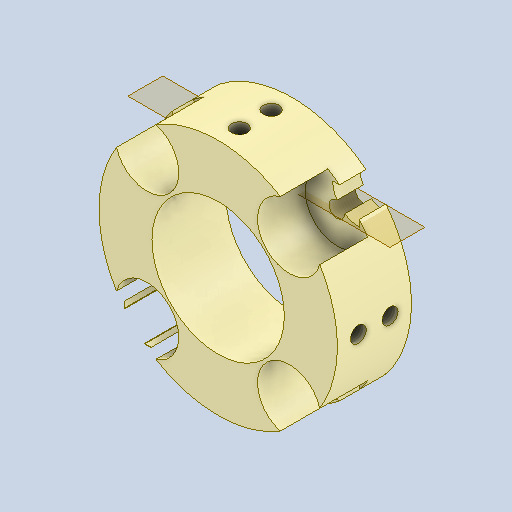
# Autodesk Inventor part: 零件1 - 副本
Saved by Autodesk Inventor 2025 (Build 290162000, 162)
## iProperties
Created: 2026-11-03
Part Number: 零件1 - 副本
Material: 尼龙 6/6
Document SubType Name: Modeling
Designer: test
Density: 1.13 g/cm^3
Appearance: 尼龙 6
Author: test
Autodesk Inventor part; units mm, degrees
ref_plane "YZ Plane" through (0, 0, 0) normal (1, 0, 0) x (0, 1, 0)
ref_plane "XY Plane" through (0, 0, 0) normal (0, 0, 1) x (1, 0, 0)
sketch "草图1" plane through (0, 0, 0) normal (0, 0, 1) x (1, 0, 0)
  circle A0 centre (0, 0) radius 22.5
  dimension "d0" = 45
  constraints: 1 centre point, 1 coincident
  measures "d0" diameter of A0
extrude "拉伸1" add sketch "草图1" along normal blind 8
sketch "草图2" plane through (0, 0, 8) normal (0, 0, 1) x (1, 0, 0)
  circle A0 centre (0, 0) radius 19
  line L0 (-13.435, -13.435) -> (13.435, -13.435)
  line L1 (13.435, -13.435) -> (13.435, 13.435)
  line L2 (13.435, 13.435) -> (-13.435, 13.435)
  line L3 (-13.435, 13.435) -> (-13.435, -13.435)
  line L4 (-13.435, -13.435) -> (13.435, 13.435) construction
  line L5 (13.435, -13.435) -> (-13.435, 13.435) construction
  circle A1 centre (-13.435, 13.435) radius 1.5
  circle A2 centre (13.435, 13.435) radius 1.5
  circle A3 centre (13.435, -13.435) radius 1.5
  circle A4 centre (-13.435, -13.435) radius 1.5
  dimension "d3" = 38
  dimension "d4" = 3
  dimension "d5" = 3
  dimension "d6" = 3
  dimension "d7" = 3
  constraints: 12 end point, 5 centre point, 4 coincident, 2 midpoint, 2 parallel, 2 perpendicular, 2 point on circle, 1 horizontal
  measures "d3" diameter of A0
  measures "d4" diameter of A1
  measures "d5" diameter of A2
  measures "d6" diameter of A3
  measures "d7" diameter of A4
extrude "拉伸2" cut sketch "草图2" against normal through all contours A2 L1 A0 | A0 A2 | A3 A0 | A0 L1 A3 | L2 A2 A0 | L1 A2 L2 | A0 A3 L0 | L0 A3 L1 | A1 L2 A0 | A0 A1 | A1 L3 L2 | A4 A0 | A0 L0 A4 | L0 L3 A4 | L3 A1 A0 | A0 A4 L3
ref_plane "工作平面1" through (0, 13.5, 0) normal (0, 1, 0) x (-1, 0, 0)
sketch "草图4" plane through (0, 13.5, 0) normal (0, 1, 0) x (-1, 0, 0)
  circle A0 centre (0, 4) radius 1.5
  line L0 (22.5, 8) -> (-22.5, 8) projected
  point P0 (0, 0)
  dimension "d13" = 3
  dimension "d14" = 4
  constraints: 1 centre point
  measures "d13" diameter of A0
  measures "d14" distance from line of A0.centre L0
extrude "拉伸3" cut sketch "草图4" along normal blind 10
thread "螺纹1" size "M3x0.5" designation "M3" class "6H" standard "GB Metric profile" length 15.103
pattern_circular "环形阵列1" count 4 over 360 about axis through (0, 0, 0) along (0, 0, 1) of "拉伸3"
thread "螺纹2" size "M3x0.5" designation "M3" class "6H" standard "GB Metric profile" length 15.103
thread "螺纹3" size "M3x0.5" designation "M3" class "6H" standard "GB Metric profile" length 15.103
thread "螺纹4" size "M3x0.5" designation "M3" class "6H" standard "GB Metric profile" length 15.103
thread "螺纹5" size "M3x0.5" designation "M3" class "6H" standard "GB Metric profile" length 15.103
sketch "草图5" plane through (0, 0, 8) normal (0, 0, 1) x (1, 0, 0)
  circle A0 centre (13.435, -13.435) radius 1.5 projected
  circle A1 centre (13.435, 13.435) radius 1.5 projected
  circle A2 centre (-13.435, -13.435) radius 1.5 projected
  circle A3 centre (-13.435, 13.435) radius 1.5 projected
  circle A4 centre (0, 0) radius 22.5 projected
  circle A5 centre (-13.435, -13.435) radius 3
  circle A6 centre (-13.435, 13.435) radius 3
  circle A7 centre (13.435, 13.435) radius 3
  circle A8 centre (13.435, -13.435) radius 3
  dimension "d30" = 6
  dimension "d31" = 6
  dimension "d32" = 6
  dimension "d33" = 6
  constraints: 4 centre point, 4 coincident
  measures "d30" diameter of A5
  measures "d31" diameter of A6
  measures "d32" diameter of A7
  measures "d33" diameter of A8
extrude "拉伸4" cut sketch "草图5" against normal blind 3 contours A5 | A6 | A7 | A8
sketch "草图6" plane through (0, 0, 8) normal (0, 0, 1) x (1, 0, 0)
  circle A0 centre (0, 0) radius 25
  line L0 (-17.6777, -17.6777) -> (17.6777, -17.6777)
  line L1 (17.6777, -17.6777) -> (17.6777, 17.6777)
  line L2 (17.6777, 17.6777) -> (-17.6777, 17.6777)
  line L3 (-17.6777, 17.6777) -> (-17.6777, -17.6777)
  line L4 (-17.6777, -17.6777) -> (17.6777, 17.6777) construction
  line L5 (17.6777, -17.6777) -> (-17.6777, 17.6777) construction
  circle A1 centre (-17.6777, 17.6777) radius 5.05
  circle A2 centre (17.6777, 17.6777) radius 5.05
  circle A3 centre (17.6777, -17.6777) radius 5.05
  circle A4 centre (-17.6777, -17.6777) radius 5.05
  point P0 (-12.6277, -17.6777)
  point P1 (-17.6777, -12.6277)
  point P2 (17.6777, -12.6277)
  point P3 (12.6277, -17.6777)
  point P4 (12.6277, 17.6777)
  point P5 (17.6777, 12.6277)
  point P6 (-17.6777, 12.6277)
  point P7 (-12.6277, 17.6777)
  dimension "d36" = 50
  dimension "d37" = 10.1
  dimension "d38" = 10.1
  dimension "d39" = 10.1
  dimension "d40" = 10.1
  constraints: 12 end point, 5 coincident, 4 centre point, 2 midpoint, 2 parallel, 2 perpendicular, 1 horizontal, 3 other
  measures "d37" diameter of A1
  measures "d38" diameter of A2
  measures "d39" diameter of A3
  measures "d40" diameter of A4
extrude "拉伸5" cut sketch "草图6" against normal blind 8 contours L1 A2 L2 | L0 A3 L1 | A1 L3 L2 | L0 L3 A4
sketch "草图7" plane through (0, 0, 8) normal (0, 0, 1) x (1, 0, 0)
  arc A0 (17.6777, -12.6277) -> (16.3672, -12.8007) centre (17.6777, -17.6777) ccw projected
  line L0 (17.6777, -12.6277) -> (17.6777, -13.9194) projected
  arc A1 (17.6777, -13.9194) -> (17.6777, 13.9194) centre (0, 0) ccw projected
  line L1 (17.6777, 13.9194) -> (17.6777, 12.6277) projected
  arc A2 (16.3672, 12.8007) -> (17.6777, 12.6277) centre (17.6777, 17.6777) ccw projected
  arc A3 (12.8007, 16.3672) -> (16.3672, 12.8007) centre (13.435, 13.435) ccw projected
  arc A4 (12.6277, 17.6777) -> (12.8007, 16.3672) centre (17.6777, 17.6777) ccw projected
  line L2 (12.6277, 17.6777) -> (13.9194, 17.6777) projected
  arc A5 (13.9194, 17.6777) -> (-13.9194, 17.6777) centre (0, 0) ccw projected
  line L3 (-13.9194, 17.6777) -> (-12.6277, 17.6777) projected
  arc A6 (-12.8007, 16.3672) -> (-12.6277, 17.6777) centre (-17.6777, 17.6777) ccw projected
  arc A7 (-16.3672, 12.8007) -> (-12.8007, 16.3672) centre (-13.435, 13.435) ccw projected
  arc A8 (-17.6777, 12.6277) -> (-16.3672, 12.8007) centre (-17.6777, 17.6777) ccw projected
  line L4 (-17.6777, 12.6277) -> (-17.6777, 13.9194) projected
  arc A9 (-17.6777, 13.9194) -> (-17.6777, -13.9194) centre (0, 0) ccw projected
  line L5 (-17.6777, -13.9194) -> (-17.6777, -12.6277) projected
  arc A10 (-16.3672, -12.8007) -> (-17.6777, -12.6277) centre (-17.6777, -17.6777) ccw projected
  arc A11 (-12.8007, -16.3672) -> (-16.3672, -12.8007) centre (-13.435, -13.435) ccw projected
  arc A12 (-12.6277, -17.6777) -> (-12.8007, -16.3672) centre (-17.6777, -17.6777) ccw projected
  line L6 (-12.6277, -17.6777) -> (-13.9194, -17.6777) projected
  arc A13 (-13.9194, -17.6777) -> (13.9194, -17.6777) centre (0, 0) ccw projected
  line L7 (13.9194, -17.6777) -> (12.6277, -17.6777) projected
  arc A14 (12.8007, -16.3672) -> (12.6277, -17.6777) centre (17.6777, -17.6777) ccw projected
  arc A15 (16.3672, -12.8007) -> (12.8007, -16.3672) centre (13.435, -13.435) ccw projected
extrude "拉伸6" add sketch "草图7" along normal blind 6
pattern_linear "矩形阵列1" count 2 spacing 6 along (0, 0, 1) of "拉伸3", "环形阵列1", "拉伸1"
sketch "草图9" plane through (-12.6277, -17.6777, 6) normal (0, 0, -1) x (-1, 0, 0)
  line L0 (1.2917, 0) -> (0, 0) projected
  arc A0 (1.2917, 0) -> (5.05, 3.7583) centre (-12.6277, 17.6777) ccw projected
  line L1 (5.05, 5.05) -> (5.05, 3.7583) projected
  arc A1 (5.05, 5.05) -> (3.7395, 4.877) centre (5.05, 0) ccw projected
  arc A2 (3.7395, 4.877) -> (0.173, 1.3105) centre (0.8074, 4.2426) ccw projected
  arc A3 (0.173, 1.3105) -> (0, 0) centre (5.05, 0) ccw projected
  line L2 (5.05, 31.5971) -> (5.05, 30.3053) projected
  arc A4 (5.05, 31.5971) -> (1.2917, 35.3553) centre (-12.6277, 17.6777) ccw projected
  line L3 (0, 35.3553) -> (1.2917, 35.3553) projected
  arc A5 (0, 35.3553) -> (0.173, 34.0449) centre (5.05, 35.3553) ccw projected
  arc A6 (0.173, 34.0449) -> (3.7395, 30.4783) centre (0.8074, 31.1127) ccw projected
  arc A7 (3.7395, 30.4783) -> (5.05, 30.3053) centre (5.05, 35.3553) ccw projected
  line L4 (-30.3053, 30.3053) -> (-30.3053, 31.5971) projected
  arc A8 (-30.3053, 30.3053) -> (-28.9949, 30.4783) centre (-30.3053, 35.3553) ccw projected
  arc A9 (-28.9949, 30.4783) -> (-25.4283, 34.0449) centre (-26.0627, 31.1127) ccw projected
  arc A10 (-25.4283, 34.0449) -> (-25.2553, 35.3553) centre (-30.3053, 35.3553) ccw projected
  line L5 (-26.5471, 35.3553) -> (-25.2553, 35.3553) projected
  arc A11 (-26.5471, 35.3553) -> (-30.3053, 31.5971) centre (-12.6277, 17.6777) ccw projected
  line L6 (-25.2553, 0) -> (-26.5471, 0) projected
  arc A12 (-25.2553, 0) -> (-25.4283, 1.3105) centre (-30.3053, 0) ccw projected
  arc A13 (-25.4283, 1.3105) -> (-28.9949, 4.877) centre (-26.0627, 4.2426) ccw projected
  arc A14 (-28.9949, 4.877) -> (-30.3053, 5.05) centre (-30.3053, 0) ccw projected
  line L7 (-30.3053, 3.7583) -> (-30.3053, 5.05) projected
  arc A15 (-30.3053, 3.7583) -> (-26.5471, 0) centre (-12.6277, 17.6777) ccw projected
extrude "拉伸8" cut sketch "草图9" against normal blind 16.5
sketch "草图10" plane through (0, 0, 14) normal (0, 0, 1) x (1, 0, 0)
  circle A0 centre (0, 0) radius 12.5
  dimension "d52" = 25
  constraints: 1 centre point, 1 coincident
  measures "d52" diameter of A0
extrude "拉伸9" cut sketch "草图10" against normal through all
sketch "草图12" plane through (0, 0, 14) normal (0, 0, 1) x (1, 0, 0)
  arc A0 (-12.8007, -16.3672) -> (-16.3672, -12.8007) centre (-13.435, -13.435) ccw projected
  arc A1 (-12.6277, -17.6777) -> (-13.4373, -14.935) centre (-17.6777, -17.6777) ccw projected
  circle A2 centre (-13.435, -13.435) radius 4.3188
  circle A3 centre (0, 0) radius 12.5 projected
  line L0 (17.6777, 13.9194) -> (17.6777, 12.6277) projected
  arc A4 (16.3672, 12.8007) -> (17.6777, 12.6277) centre (17.6777, 17.6777) ccw projected
  arc A5 (12.8007, 16.3672) -> (16.3672, 12.8007) centre (13.435, 13.435) ccw projected
  arc A6 (12.6277, 17.6777) -> (12.8007, 16.3672) centre (17.6777, 17.6777) ccw projected
  line L1 (12.6277, 17.6777) -> (13.9194, 17.6777) projected
  arc A7 (13.9194, 17.6777) -> (-13.9194, 17.6777) centre (0, 0) ccw projected
  line L2 (-13.9194, 17.6777) -> (-12.6277, 17.6777) projected
  arc A8 (-12.8007, 16.3672) -> (-12.6277, 17.6777) centre (-17.6777, 17.6777) ccw projected
  arc A9 (-16.3672, 12.8007) -> (-12.8007, 16.3672) centre (-13.435, 13.435) ccw projected
  arc A10 (-17.6777, 12.6277) -> (-16.3672, 12.8007) centre (-17.6777, 17.6777) ccw projected
  line L3 (-17.6777, 12.6277) -> (-17.6777, 13.9194) projected
  arc A11 (-17.6777, 13.9194) -> (-17.6777, -13.9194) centre (0, 0) ccw projected
  line L4 (-17.6777, -13.9194) -> (-17.6777, -12.6277) projected
  arc A12 (-16.3672, -12.8007) -> (-17.6777, -12.6277) centre (-17.6777, -17.6777) ccw projected
  arc A13 (-12.8007, -16.3672) -> (-16.3672, -12.8007) centre (-13.435, -13.435) ccw projected
  arc A14 (-12.6277, -17.6777) -> (-12.8007, -16.3672) centre (-17.6777, -17.6777) ccw projected
  line L5 (-12.6277, -17.6777) -> (-13.9194, -17.6777) projected
  arc A15 (-13.9194, -17.6777) -> (13.9194, -17.6777) centre (0, 0) ccw projected
  line L6 (13.9194, -17.6777) -> (12.6277, -17.6777) projected
  arc A16 (12.8007, -16.3672) -> (12.6277, -17.6777) centre (17.6777, -17.6777) ccw projected
  arc A17 (16.3672, -12.8007) -> (12.8007, -16.3672) centre (13.435, -13.435) ccw projected
  arc A18 (17.6777, -12.6277) -> (16.3672, -12.8007) centre (17.6777, -17.6777) ccw projected
  line L7 (17.6777, -12.6277) -> (17.6777, -13.9194) projected
  arc A19 (17.6777, -13.9194) -> (17.6777, 13.9194) centre (0, 0) ccw projected
  arc A20 (-14.935, 13.4373) -> (-13.4373, 14.935) centre (-13.435, 13.435) ccw projected
  circle A21 centre (-13.435, 13.435) radius 6
  circle A22 centre (-13.435, -13.435) radius 6
  circle A23 centre (13.435, -13.435) radius 6
  circle A24 centre (13.435, 13.435) radius 6
  point P0 (11.7441, 19.1918)
  point P1 (19.1918, 11.7441)
  point P2 (-19.1918, 11.7441)
  point P3 (-11.7441, 19.1918)
  point P4 (19.1918, -11.7441)
  point P5 (11.7441, -19.1918)
  point P6 (-19.1918, -11.7441)
  point P7 (-17.7341, -13.8475)
  point P8 (-13.8475, -17.7341)
  point P9 (-11.7441, -19.1918)
  constraints: 5 coincident, 15 other
extrude "拉伸10" cut sketch "草图12" against normal up to surface (9 mm away) contours A0 A12 A2 A1 | A2 A11 A22 A15 | A23 A19 L7 A18 A17 A16 L6 A15 | A11 L3 A10 A9 A8 L2 A7 A21 | A24 A7 L1 A6 A5 A4 L0 A19 picked at (-8.0518, -12.9635) picked at (17.3649, -10.3928) picked at (-8.4939, 12.8925) picked at (10.3928, 17.3649)
